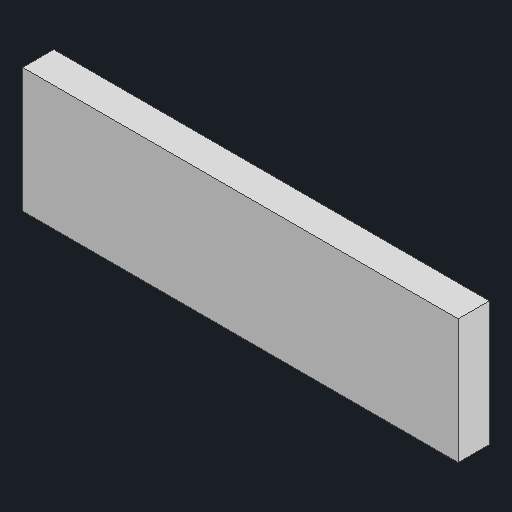
# Autodesk Inventor part: P4-05 Foam contact pad
Saved by Autodesk Inventor 2027.1 (Build 311270010, 270A)
## iProperties
Created: 2026-10-21
Part Number: P4-05 Foam contact pad
Material: Generic
Document SubType Name: Modeling
Designer: anshi
Mass: 0.448 g
Surface Area: 5.92 cm^2
Volume: 0.448 cm^3
Density: 1 g/cm^3
Appearance: Default
Author: anshi
Autodesk Inventor part; units mm, degrees
ref_plane "YZ Plane" through (0, 0, 0) normal (1, 0, 0) x (0, 1, 0)
ref_plane "XZ Plane" through (0, 0, 0) normal (0, 1, 0) x (-1, 0, 0)
ref_plane "XY Plane" through (0, 0, 0) normal (0, 0, 1) x (1, 0, 0)
sketch "Dimensioned base profile" plane through (0, 0, 0) normal (0, 0, 1) x (1, 0, 0)
  line L0 (0, 0) -> (28, 0)
  line L1 (28, 0) -> (28, 8)
  line L2 (28, 8) -> (0, 8)
  line L3 (0, 8) -> (0, 0)
  constraints: 8 end point
extrude "Thickness 2 mm" add sketch "Dimensioned base profile" along normal blind 2
equation "\"NominalThickness\" = 2"
body "Solid1"
